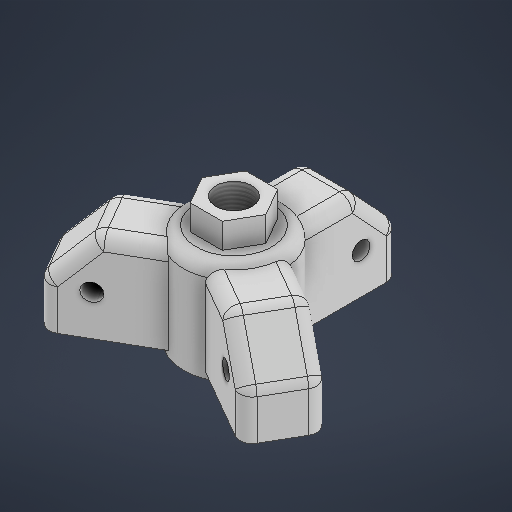
# Autodesk Inventor part: Part3
Saved by Autodesk Inventor 2025.4 (Build 294407000, 407)
## iProperties
Created: 2026-06-25
Part Number: Part3
Material: Generic
Document SubType Name: Modeling
Designer: VuQuan
Density: 1 g/cm^3
Appearance: Default
Author: VuQuan
Autodesk Inventor part; units mm, degrees
ref_plane "YZ Plane" through (0, 0, 0) normal (1, 0, 0) x (0, 1, 0)
ref_plane "XZ Plane" through (0, 0, 0) normal (0, 1, 0) x (-1, 0, 0)
ref_plane "XY Plane" through (0, 0, 0) normal (0, 0, 1) x (1, 0, 0)
sketch "Sketch1" plane through (0, 0, 0) normal (0, 1, 0) x (-1, 0, 0)
  circle A0 centre (0, 0) radius 20
  dimension "d0" = 40
  constraints: 1 centre point, 1 coincident
  measures "d0" diameter of A0
extrude "Extrusion1" add sketch "Sketch1" along normal blind 40
sketch "Sketch2" plane through (0, 0, 0) normal (1, 0, 0) x (0, 1, 0)
  line L0 (2.5, 0) -> (2.5, -53)
  line L1 (2.5, -53) -> (18.5, -53)
  line L2 (21.9071, -51.6595) -> (36.4071, -38.1595)
  line L3 (38, -34.5) -> (38, 0)
  circle A0 centre (18.5, -38) radius 3.5
  arc A1 (36.4071, -38.1595) -> (38, -34.5) centre (33, -34.5) ccw
  arc A2 (18.5, -53) -> (21.9071, -51.6595) centre (18.5, -48) ccw
  line L4 (38, 0) -> (0, 0)
  point P0 (18.5, -34.5)
  dimension "d8" = 7
  dimension "d3" = 53
  dimension "d9" = 38
  dimension "d10" = 16
  dimension "d13" = 5
  dimension "d14" = 5
  dimension "d16" = 19.5
  dimension "d23" = 2.5
  constraints: 10 end point, 4 point on circle, 4 tangent, 3 vertical alignment, 2 centre point, 2 horizontal alignment, 1 horizontal, 1 parallel, 1 perpendicular, 1 point on line, 1 vertical, 2 other
  measures "d3" distance from line of L1 L4.end
  measures "d9" vertical distance of L4.end point (18.5, -38)
  measures "d10" distance from line of L0 point (18.5, -38)
  measures "d13" radius of A1
  measures "d14" radius of A2
  measures "d16" distance from line of point (18.5, -38) L3
  measures "d23" distance from line of L4.end L0
extrude "Extrusion2" add sketch "Sketch2" along normal mid plane 25
fillet "Fillet1" radius 5 10 edges at (12.5, 37.5845, -36.4956) (12.5, 38, -25.0562) (12.5, 20.3307, -52.6528) (12.5, 10.5, -53) (12.5, 29.1571, -44.9095) (-12.5, 20.3307, -52.6528) (-12.5, 10.5, -53) (-12.5, 37.5845, -36.4956) (-12.5, 38, -25.0562) (-12.5, 29.1571, -44.9095)
pattern_circular "Circular Pattern1" count 3 over 360 about axis through (0, 0, 0) along (0, 1, 0) of "Extrusion2", "Fillet1"
sketch "Sketch3" plane through (0, 40, 0) normal (0, 1, 0) x (1, 0, 0)
  circle A0 centre (0, 0) radius 20 projected
  line L0 (-12.7017, 0) -> (-6.3509, 11)
  line L1 (-6.3509, 11) -> (6.3509, 11)
  line L2 (6.3509, 11) -> (12.7017, 0)
  line L3 (12.7017, 0) -> (6.3509, -11)
  line L4 (6.3509, -11) -> (-6.3509, -11)
  line L5 (-6.3509, -11) -> (-12.7017, 0)
  dimension "d24" = 22
  constraints: 12 end point, 1 coincident, 1 horizontal alignment, 13 other
  measures "d24" distance between parallel lines of L1 L4
extrude "Extrusion3" add sketch "Sketch3" along normal blind 10 contours L0 L1 L2 L3 L4 L5
hole "Hole1" at (0, 0, 0) direction (0, 1, 0) diameter 14.376 end through all thread size "M16x1.5" class "6H" standard "ISO Metric profile"
fillet "Fillet2" radius 5 1 edges at (20, 40, 0)
body "Solid1"
